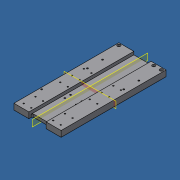
# Autodesk Inventor part: Esempio-002
Saved by Autodesk Inventor 2021.1 (Build 251245000, 245)
## iProperties
Created: 2022-02-23
Part Number: Esempio-002
Material: Alluminio
Document SubType Name: Modeling
Designer: UT
Mass: 4768.45 g
Surface Area: 2326.09 cm^2
Volume: 1759.57 cm^3
Density: 2.71 g/cm^3
Appearance: Default
Author: UT
Autodesk Inventor part; units mm, degrees
ref_plane "XY Plane" through (0, 0, 0) normal (0, 0, 1) x (1, 0, 0)
sketch "Schizzo16" plane through (0, 0, 0) normal (0, 0, 1) x (1, 0, 0)
  line L0 (-100, 222.5) -> (100, 222.5)
  line L1 (100, 222.5) -> (100, -222.5)
  line L2 (100, -222.5) -> (-100, -222.5)
  line L3 (-100, -222.5) -> (-100, 222.5)
  line L4 (-100, 222.5) -> (100, -222.5) construction
  line L5 (100, 222.5) -> (-100, -222.5) construction
  point P0 (0, 0)
  dimension "d68" = 200
  dimension "d69" = 445
  constraints: 12 end point, 2 midpoint, 2 parallel, 1 horizontal, 1 perpendicular
  measures "d68" distance of L1.end L2.end
  measures "d69" distance of L0.end L1.end
extrude "Estrusione5" add sketch "Schizzo16" along normal blind 25
sketch "Schizzo17" plane through (0, 0, 25) normal (0, 0, 1) x (1, 0, 0)
  line L0 (-100, -222.5) -> (100, -222.5) projected
  line L1 (100, 222.5) -> (-100, 222.5) projected
  line L2 (-36.5, -222.5) -> (36.5, -222.5)
  line L3 (36.5, -222.5) -> (36.5, 222.5)
  line L4 (36.5, 222.5) -> (-36.5, 222.5)
  line L5 (-36.5, 222.5) -> (-36.5, -222.5)
  line L6 (-36.5, -222.5) -> (36.5, 222.5) construction
  line L7 (36.5, -222.5) -> (-36.5, 222.5) construction
  point P0 (0, 0)
  point P1 (-36.5, -222.5)
  point P2 (36.5, -222.5)
  dimension "d72" = 73
  constraints: 12 end point, 2 midpoint, 2 parallel, 1 horizontal, 1 perpendicular, 1 point on line
  measures "d72" distance between parallel lines of L5 L3
extrude "Estrusione6" cut sketch "Schizzo17" against normal blind 10
sketch "Schizzo18" plane through (0, 0, 0) normal (0, 0, -1) x (-1, 0, 0)
  line L0 (-78.5, 2.5) -> (-46.5, 2.5) construction
  line L1 (-62.5, -5.321) -> (-62.5, -29.5697) construction
  line L2 (100, -222.5) -> (-100, -222.5) projected
  point P0 (0, 0)
  point P1 (-46.5, -47.5)
  point P2 (-78.5, -47.5)
  point P3 (-78.5, -152.5)
  point P4 (-46.5, -152.5)
  point P5 (-46.5, -202.5)
  point P6 (-78.5, -202.5)
  point P7 (-78.5, 52.5)
  point P8 (-46.5, 52.5)
  dimension "d75" = 32
  dimension "d76" = 50
  dimension "d77" = 50
  dimension "d88" = 62.5
  dimension "d89" = 16
  dimension "d91" = 20
  dimension "d95" = 155
  dimension "d96" = 50
  constraints: 8 vertical alignment, 5 horizontal alignment, 4 end point, 1 horizontal, 1 vertical
  measures "d75" distance of L0.end L0.start
  measures "d76" distance of point (-78.5, -47.5) L0.start
  measures "d77" distance of point (-78.5, -152.5) point (-78.5, -202.5)
  measures "d88" distance from line of point (0, 0) L1
  measures "d89" distance from line of L1 L0.start
  measures "d91" distance from line of L2 point (-78.5, -202.5)
  measures "d95" distance of L0.start point (-78.5, -152.5)
  measures "d96" distance of L0.start point (-78.5, 52.5)
hole "Foro4" at (78.5, 2.5, 0) at (46.5, 2.5, 0) at (46.5, -47.5, 0) at (78.5, -47.5, 0) at (78.5, -152.5, 0) at (46.5, -152.5, 0) at (46.5, -202.5, 0) at (78.5, -202.5, 0) at (46.5, 52.5, 0) at (78.5, 52.5, 0) direction (0, 0, 1) diameter 5.5 end through all counterbore diameter 9 counterbore depth 5.5 clearance for "Brugola" size "M5" standard "Angeleri"
mirror "Specchio1" about plane through (0, 0, 0) normal (1, 0, 0) of "Foro4"
sketch "Schizzo19" plane through (0, 0, 15) normal (0, 0, 1) x (1, 0, 0)
  line L0 (36.5, -222.5) -> (-36.5, -222.5) projected
  line L1 (36.5, 222.5) -> (36.5, -222.5) projected
  line L2 (-36.5, -222.5) -> (-36.5, 222.5) projected
  line L3 (36.5, -222.5) -> (-36.5, -222.5)
  line L4 (-36.5, -222.5) -> (-36.5, 222.5)
  line L5 (-36.5, 222.5) -> (36.5, 222.5)
  line L6 (36.5, 222.5) -> (36.5, -222.5)
  line L7 (-100, -222.5) -> (-36.5, -222.5) projected
  point P0 (0, 0)
  point P1 (36.5, 222.5)
  dimension "d97" = 445
  constraints: 8 end point, 2 parallel, 1 horizontal, 1 perpendicular, 1 point on line
  measures "d97" distance between parallel lines of L7 L5
extrude "Estrusione7" cut sketch "Schizzo19" against normal blind 3
sketch "Schizzo20" plane through (0, 0, 0) normal (0, 0, -1) x (-1, 0, 0)
  line L0 (100, -222.5) -> (-100, -222.5) projected
  point P0 (0, 0)
  point P1 (24, -82.5)
  point P2 (-24, -82.5)
  point P3 (-24, -58.5)
  point P4 (24, -58.5)
  dimension "d101" = 48
  dimension "d102" = 24
  dimension "d103" = 24
  dimension "d104" = 140
  constraints: 2 horizontal alignment, 2 vertical alignment
  measures "d101" distance of point (-24, -82.5) point (24, -82.5)
  measures "d102" distance of point (24, -58.5) point (24, -82.5)
  measures "d103" horizontal distance of point (0, 0) point (24, -82.5)
  measures "d104" distance from line of point (-24, -82.5) L0
hole "Foro5" at (-24, -82.5, 0) at (24, -82.5, 0) at (24, -58.5, 0) at (-24, -58.5, 0) direction (0, 0, 1) diameter 6.5 end through all counterbore diameter 10.5 counterbore depth 6.5
sketch "Schizzo21" plane through (-100, -222.5, 0) normal (0, -1, 0) x (1, 0, 0)
  line L0 (0, 0) -> (200, 0) projected
  line L1 (136.5, 25) -> (136.5, 12) projected
  line L2 (136.5, 12) -> (63.5, 12) projected
  line L3 (63.5, 12) -> (136.5, 12)
  line L4 (136.5, 12) -> (136.5, 2)
  line L5 (136.5, 2) -> (63.5, 2)
  line L6 (63.5, 2) -> (63.5, 12)
  point P0 (100, 0)
  dimension "d112" = 2
  constraints: 8 end point, 2 parallel, 1 collinear, 1 horizontal, 1 perpendicular
  measures "d112" distance between parallel lines of L5 L0
extrude "Estrusione8" cut sketch "Schizzo21" against normal blind 15
fillet "Raccordo2" radius 6 2 edges at (36.5, -207.5, 7) (-36.5, -207.5, 7)
sketch "Schizzo22" plane through (-100, -222.5, 0) normal (-1, 0, 0) x (0, 0, 1)
  line L0 (0, 445) -> (0, 0) projected
  line L1 (0, 0) -> (25, 0) projected
  point P0 (0, 222.5)
  point P1 (12, 22)
  point P2 (12, 47)
  dimension "d116" = 25
  dimension "d117" = 12
  dimension "d118" = 22
  constraints: 1 vertical alignment
  measures "d116" distance of point (12, 22) point (12, 47)
  measures "d117" distance from line of L0 point (12, 22)
  measures "d118" distance from line of point (12, 22) L1
hole "Foro6" at (-100, -200.5, 12) at (-100, -175.5, 12) direction (1, 0, 0) diameter 4.134 depth 15 tip angle 118 thread size "M5x0.8" class "6H" standard "ISO Metric profile"
sketch "Schizzo23" plane through (0, 0, 25) normal (0, 0, 1) x (1, 0, 0)
  line L0 (-100, 222.5) -> (-100, -222.5) projected
  line L1 (-100, -222.5) -> (-36.5, -222.5) projected
  point P0 (0, 0)
  point P1 (-92.5, -112.5)
  dimension "d126" = 7.5
  dimension "d127" = 110
  measures "d126" distance from line of L0 point (-92.5, -112.5)
  measures "d127" distance from line of L1 point (-92.5, -112.5)
hole "Foro7" at (-92.5, -112.5, 25) direction (0, 0, -1) diameter 6.647 depth 16 tip angle 118 thread size "M8x1.25" class "6H" standard "ISO Metric profile"
sketch "Schizzo24" plane through (-36.5, -222.5, 2) normal (0, 0, 1) x (1, 0, 0)
  arc A0 (6, 15) -> (0, 9) centre (6, 9) ccw projected
  line L0 (0, 0) -> (0, 9) projected
  line L1 (73, 0) -> (0, 0) projected
  line L2 (73, 0) -> (73, 9) projected
  arc A1 (73, 9) -> (67, 15) centre (67, 9) ccw projected
  line L3 (67, 15) -> (6, 15) projected
  point P0 (36.5, 222.5)
extrude "Estrusione9" cut sketch "Schizzo24" against normal blind 10
sketch "Schizzo25" plane through (0, 0, 25) normal (0, 0, 1) x (1, 0, 0)
  line L0 (100, 222.5) -> (36.5, 222.5) projected
  line L1 (-100, 222.5) -> (-100, -222.5) projected
  line L2 (100, -222.5) -> (100, 222.5) projected
  point P0 (0, 0)
  point P1 (90, 212.5)
  point P2 (-90, 212.5)
  point P3 (58, 212.5)
  dimension "d138" = 10
  dimension "d147" = 10
  dimension "d160" = 10
  dimension "d161" = 42
  constraints: 2 horizontal alignment
  measures "d138" distance from line of point (90, 212.5) L0
  measures "d147" distance from line of L1 point (-90, 212.5)
  measures "d160" distance from line of L2 point (90, 212.5)
  measures "d161" distance from line of L2 point (58, 212.5)
hole "Foro8" at (90, 212.5, 25) at (-90, 212.5, 25) at (58, 212.5, 25) direction (0, 0, -1) diameter 8.5 end through all counterbore diameter 13.5 counterbore depth 8.5
sketch "Schizzo26" plane through (0, 0, 0) normal (0, 0, -1) x (-1, 0, 0)
  line L0 (-100, 222.5) -> (100, 222.5) projected
  line L1 (100, 222.5) -> (100, -222.5) projected
  circle A0 centre (72.4, 63) radius 4.1 projected
  circle A1 centre (-81.6, 63) radius 4.1 projected
  circle A2 centre (72.4, 127) radius 4.1 projected
  circle A3 centre (-81.6, 127) radius 4.1 projected
  point P0 (0, 0)
  point P1 (72.4, 61.5)
  point P2 (72.4, 125.5)
  point P3 (-81.6, 125.5)
  point P4 (-81.6, 61.5)
  dimension "d148" = 64
  dimension "d149" = 154
  dimension "d151" = 97
  dimension "d159" = 27.6
  constraints: 2 horizontal alignment, 2 vertical alignment
  measures "d148" distance of point (72.4, 125.5) point (72.4, 61.5)
  measures "d149" distance of point (-81.6, 125.5) point (72.4, 125.5)
  measures "d151" distance from line of point (72.4, 125.5) L0
  measures "d159" distance from line of point (72.4, 125.5) L1
hole "Foro9" at (-72.4, 61.5, 0) at (-72.4, 125.5, 0) at (81.6, 125.5, 0) at (81.6, 61.5, 0) direction (0, 0, 1) diameter 6.647 end through all thread size "M8x1.25" class "6H" standard "ISO Metric profile"
equation "\"d77\" = d76"
equation "\"d89\" = 0.5 * d75"
equation "\"d96\" = d76"
equation "\"d103\" = 0.5 * d101"
equation "\"d160\" = d147"
